Autodesk Fusion 360 part; units mm, degrees
(part 6 of 8)
equation "d534 = ( ledCenter - ledHeight / 2 + diffuserClearance + diffuserSideWall ) + faceOriginV"
equation "d535 = ( ( ( caseWidth - ledWidth ) / 2 + diffuserClearance + diffuserSideWall ) + ( ledWidth - 2 * ( diffuserClearance + diffuserSideWall ) ) ) - ( ( caseWidth - ledWidth ) / 2 + diffuserClearance + diffuserSideWall )"
equation "d536 = ( ( ( ledCenter - ledHeight / 2 + diffuserClearance + diffuserSideWall ) + faceOriginV ) + ( ledHeight - 2 * ( diffuserClearance + diffuserSideWall ) ) ) - ( ( ledCenter - ledHeight / 2 + diffuserClearance + diffuserSideWall ) + faceOriginV )"
equation "d537 = -( diffuserRearDepth + 1 mm )"
equation "d539 = ( caseWidth + ledWidth ) / 2 - diffuserSideWall - 1 mm"
equation "d540 = ( ledCenter - ledWireWidth / 2 ) + faceOriginV"
equation "d541 = ( ( ( caseWidth + ledWidth ) / 2 - diffuserSideWall - 1 mm ) + ( 5 mm ) ) - ( ( caseWidth + ledWidth ) / 2 - diffuserSideWall - 1 mm )"
equation "d542 = ( ( ( ledCenter - ledWireWidth / 2 ) + faceOriginV ) + ( ledWireWidth ) ) - ( ( ledCenter - ledWireWidth / 2 ) + faceOriginV )"
equation "d543 = -( diffuserRearDepth )"
equation "d545 = ( caseWidth - ledWidth ) / 2 + diffuserClearance - diffuserFlange - flangePocketClearance"
equation "d546 = ( ledCenter - ledHeight / 2 + diffuserClearance - diffuserFlange - flangePocketClearance ) + faceOriginV"
equation "d547 = ( ( ( caseWidth - ledWidth ) / 2 + diffuserClearance - diffuserFlange - flangePocketClearance ) + ( ledWidth - 2 * diffuserClearance + 2 * ( diffuserFlange + flangePocketClearance ) ) ) - ( ( caseWidth - ledWidth ) / 2 + diffuserClearance - diffuserFlange - flangePocketClearance )"
equation "d548 = ( ( ( ledCenter - ledHeight / 2 + diffuserClearance - diffuserFlange - flangePocketClearance ) + faceOriginV ) + ( ledHeight - 2 * diffuserClearance + 2 * ( diffuserFlange + flangePocketClearance ) ) ) - ( ( ledCenter - ledHeight / 2 + diffuserClearance - diffuserFlange - flangePocketClearance ) + faceOriginV )"
equation "d549 = -( diffuserRearDepth - shellWall - carrierClearance + 0.2 mm )"
equation "d551 = ( caseWidth - ledWidth ) / 2 - 0.2 mm"
equation "d552 = ( faceLength - ( shellWall + carrierClearance ) / cos(caseTilt) - ( shellWall + carrierClearance + carrierThickness ) * tan(caseTilt) - carrierRim + 0.4 mm ) + faceOriginV"
equation "d553 = ( ( ( caseWidth - ledWidth ) / 2 - 0.2 mm ) + ( ledWidth + 0.4 mm ) ) - ( ( caseWidth - ledWidth ) / 2 - 0.2 mm )"
equation "d554 = ( ( ( faceLength - ( shellWall + carrierClearance ) / cos(caseTilt) - ( shellWall + carrierClearance + carrierThickness ) * tan(caseTilt) - carrierRim + 0.4 mm ) + faceOriginV ) + ( 4 mm ) ) - ( ( faceLength - ( shellWall + carrierClearance ) / cos(caseTilt) - ( shellWall + carrierClearance + carrierThickness ) * tan(caseTilt) - carrierRim + 0.4 mm ) + faceOriginV )"
equation "d555 = -( ledTrayDepth + ledTrayThickness - shellWall - carrierClearance )"
equation "d557 = -ledTrayDepth"
equation "d559 = ( caseWidth - ledWidth ) / 2 - 0.2 mm"
equation "d560 = ( ledCenter - ledHeight / 2 - 0.2 mm ) + faceOriginV"
equation "d561 = ( ( ( caseWidth - ledWidth ) / 2 - 0.2 mm ) + ( ledWidth + 0.4 mm ) ) - ( ( caseWidth - ledWidth ) / 2 - 0.2 mm )"
equation "d562 = ( ( ( ledCenter - ledHeight / 2 - 0.2 mm ) + faceOriginV ) + ( ( faceLength - ( shellWall + carrierClearance ) / cos(caseTilt) - ( ledTrayDepth + ledTrayThickness ) * tan(caseTilt) ) - ( ledCenter - ledHeight / 2 - 0.2 mm ) ) ) - ( ( ledCenter - ledHeight / 2 - 0.2 mm ) + faceOriginV )"
equation "d563 = -( ledTrayThickness )"
equation "d565 = ( caseWidth + ledWidth ) / 2 - 2 mm"
equation "d566 = ( ledCenter - ledWireWidth / 2 ) + faceOriginV"
equation "d567 = ( ( ( caseWidth + ledWidth ) / 2 - 2 mm ) + ( 4 mm ) ) - ( ( caseWidth + ledWidth ) / 2 - 2 mm )"
equation "d568 = ( ( ( ledCenter - ledWireWidth / 2 ) + faceOriginV ) + ( ledWireWidth ) ) - ( ( ledCenter - ledWireWidth / 2 ) + faceOriginV )"
equation "d569 = -( ledTrayThickness + 1 mm )"
equation "d571 = layoutGap + ( displayWidth - oledBoardWidth ) / 2"
equation "d572 = ( controlCenter - oledBoardLength / 2 ) + faceOriginV"
equation "d573 = ( ( layoutGap + ( displayWidth - oledBoardWidth ) / 2 ) + ( oledBoardWidth ) ) - ( layoutGap + ( displayWidth - oledBoardWidth ) / 2 )"
equation "d574 = ( ( ( controlCenter - oledBoardLength / 2 ) + faceOriginV ) + ( 3 mm ) ) - ( ( controlCenter - oledBoardLength / 2 ) + faceOriginV )"
equation "d575 = -( oledPcbFrontDepth )"
equation "d577 = layoutGap + ( displayWidth - oledBoardWidth ) / 2"
equation "d578 = ( controlCenter + oledBoardLength / 2 - 5 mm ) + faceOriginV"
equation "d579 = ( ( layoutGap + ( displayWidth - oledBoardWidth ) / 2 ) + ( oledBoardWidth ) ) - ( layoutGap + ( displayWidth - oledBoardWidth ) / 2 )"
equation "d580 = ( ( ( controlCenter + oledBoardLength / 2 - 5 mm ) + faceOriginV ) + ( 3 mm ) ) - ( ( controlCenter + oledBoardLength / 2 - 5 mm ) + faceOriginV )"
equation "d581 = -( oledPcbFrontDepth )"
equation "d583 = layoutGap + ( displayWidth - oledBoardWidth ) / 2 - oledFitClearance"
equation "d584 = ( controlCenter - oledBoardLength / 2 - oledFitClearance ) + faceOriginV"
equation "d585 = ( ( layoutGap + ( displayWidth - oledBoardWidth ) / 2 - oledFitClearance ) + ( oledBoardWidth + 2 * oledFitClearance ) ) - ( layoutGap + ( displayWidth - oledBoardWidth ) / 2 - oledFitClearance )"
equation "d586 = ( ( ( controlCenter - oledBoardLength / 2 - oledFitClearance ) + faceOriginV ) + ( oledBoardLength + 2 * oledFitClearance ) ) - ( ( controlCenter - oledBoardLength / 2 - oledFitClearance ) + faceOriginV )"
equation "d587 = -( oledBackDepth + oledFitClearance - shellWall - carrierClearance )"
equation "d589 = -( oledBackDepth + oledFitClearance )"
equation "d592 = ( controlCenter - 18 mm ) + faceOriginV"
equation "d593 = ( ( 18 mm ) + ( 14 mm ) ) - ( 18 mm )"
equation "d594 = ( ( ( controlCenter - 18 mm ) + faceOriginV ) + ( 1 mm ) ) - ( ( controlCenter - 18 mm ) + faceOriginV )"
equation "d595 = -( oledBackDepth + oledFitClearance + 2 mm - shellWall - carrierClearance )"
equation "d598 = ( controlCenter - 18 mm ) + faceOriginV"
equation "d599 = ( ( 18 mm ) + ( 14 mm ) ) - ( 18 mm )"
equation "d600 = ( ( ( controlCenter - 18 mm ) + faceOriginV ) + ( 4 mm ) ) - ( ( controlCenter - 18 mm ) + faceOriginV )"
equation "d601 = -( 2 mm )"
equation "d604 = ( controlCenter + 12.8 mm ) + faceOriginV"
equation "d605 = ( ( 18 mm ) + ( 14 mm ) ) - ( 18 mm )"
equation "d606 = ( ( ( controlCenter + 12.8 mm ) + faceOriginV ) + ( 3.8 mm ) ) - ( ( controlCenter + 12.8 mm ) + faceOriginV )"
equation "d607 = -( ledTrayThickness )"
equation "d610 = ( controlCenter + 13 mm ) + faceOriginV"
equation "d611 = ( ( 18 mm ) + ( 14 mm ) ) - ( 18 mm )"
equation "d612 = ( ( ( controlCenter + 13 mm ) + faceOriginV ) + ( 2 mm ) ) - ( ( controlCenter + 13 mm ) + faceOriginV )"
equation "d613 = -( 2 mm )"
equation "d615 = layoutGap + ( displayWidth - oledBoardWidth ) / 2 - oledFitClearance"
equation "d616 = ( controlCenter - oledBoardLength / 2 - oledFitClearance ) + faceOriginV"
equation "d617 = ( ( layoutGap + ( displayWidth - oledBoardWidth ) / 2 - oledFitClearance ) + ( oledBoardWidth + 2 * oledFitClearance ) ) - ( layoutGap + ( displayWidth - oledBoardWidth ) / 2 - oledFitClearance )"
equation "d618 = ( ( ( controlCenter - oledBoardLength / 2 - oledFitClearance ) + faceOriginV ) + ( oledBoardLength + 2 * oledFitClearance ) ) - ( ( controlCenter - oledBoardLength / 2 - oledFitClearance ) + faceOriginV )"
equation "d619 = -( oledBackDepth + oledFitClearance - shellWall - carrierClearance )"
equation "d621 = pcbTopHeight + 4 mm"
equation "d624 = ( pcbFront + ( pcbLength - pcbHolePitchY ) / 2 + 0 * pcbHolePitchY ) - 2 mm"
equation "d625 = ( ( 3.2 mm ) + ( 1.6 mm ) ) - ( 3.2 mm )"
equation "d626 = ( ( ( pcbFront + ( pcbLength - pcbHolePitchY ) / 2 + 0 * pcbHolePitchY ) - 2 mm ) + ( 4 mm ) ) - ( ( pcbFront + ( pcbLength - pcbHolePitchY ) / 2 + 0 * pcbHolePitchY ) - 2 mm )"
equation "d630 = ( pcbFront + ( pcbLength - pcbHolePitchY ) / 2 + 0 * pcbHolePitchY ) - 2 mm"
equation "d631 = ( ( 3.2 mm ) + ( 3.8 mm ) ) - ( 3.2 mm )"
equation "d632 = ( ( ( pcbFront + ( pcbLength - pcbHolePitchY ) / 2 + 0 * pcbHolePitchY ) - 2 mm ) + ( 4 mm ) ) - ( ( pcbFront + ( pcbLength - pcbHolePitchY ) / 2 + 0 * pcbHolePitchY ) - 2 mm )"
equation "d635 = pcbLeft + ( pcbWidth - pcbHolePitchX ) / 2 + 0 * pcbHolePitchX"
equation "d636 = pcbFront + ( pcbLength - pcbHolePitchY ) / 2 + 0 * pcbHolePitchY"
equation "d637 = pcbPostDiameter"
equation "d640 = pcbLeft + ( pcbWidth - pcbHolePitchX ) / 2 + 0 * pcbHolePitchX"
equation "d641 = pcbFront + ( pcbLength - pcbHolePitchY ) / 2 + 0 * pcbHolePitchY"
equation "d642 = pcbPostPilot"
equation "d645 = caseWidth - 4.8 mm"
equation "d646 = ( pcbFront + ( pcbLength - pcbHolePitchY ) / 2 + 0 * pcbHolePitchY ) - 2 mm"
equation "d647 = ( ( caseWidth - 4.8 mm ) + ( 1.6 mm ) ) - ( caseWidth - 4.8 mm )"
equation "d648 = ( ( ( pcbFront + ( pcbLength - pcbHolePitchY ) / 2 + 0 * pcbHolePitchY ) - 2 mm ) + ( 4 mm ) ) - ( ( pcbFront + ( pcbLength - pcbHolePitchY ) / 2 + 0 * pcbHolePitchY ) - 2 mm )"
equation "d651 = caseWidth - 7 mm"
equation "d652 = ( pcbFront + ( pcbLength - pcbHolePitchY ) / 2 + 0 * pcbHolePitchY ) - 2 mm"
equation "d653 = ( ( caseWidth - 7 mm ) + ( 3.8 mm ) ) - ( caseWidth - 7 mm )"
equation "d654 = ( ( ( pcbFront + ( pcbLength - pcbHolePitchY ) / 2 + 0 * pcbHolePitchY ) - 2 mm ) + ( 4 mm ) ) - ( ( pcbFront + ( pcbLength - pcbHolePitchY ) / 2 + 0 * pcbHolePitchY ) - 2 mm )"
equation "d657 = pcbLeft + ( pcbWidth - pcbHolePitchX ) / 2 + 1 * pcbHolePitchX"
equation "d658 = pcbFront + ( pcbLength - pcbHolePitchY ) / 2 + 0 * pcbHolePitchY"
equation "d659 = pcbPostDiameter"
equation "d662 = pcbLeft + ( pcbWidth - pcbHolePitchX ) / 2 + 1 * pcbHolePitchX"
equation "d663 = pcbFront + ( pcbLength - pcbHolePitchY ) / 2 + 0 * pcbHolePitchY"
equation "d664 = pcbPostPilot"
equation "d668 = ( pcbFront + ( pcbLength - pcbHolePitchY ) / 2 + 1 * pcbHolePitchY ) - 2 mm"
equation "d669 = ( ( 3.2 mm ) + ( 1.6 mm ) ) - ( 3.2 mm )"
equation "d670 = ( ( ( pcbFront + ( pcbLength - pcbHolePitchY ) / 2 + 1 * pcbHolePitchY ) - 2 mm ) + ( 4 mm ) ) - ( ( pcbFront + ( pcbLength - pcbHolePitchY ) / 2 + 1 * pcbHolePitchY ) - 2 mm )"
equation "d674 = ( pcbFront + ( pcbLength - pcbHolePitchY ) / 2 + 1 * pcbHolePitchY ) - 2 mm"
equation "d675 = ( ( 3.2 mm ) + ( 3.8 mm ) ) - ( 3.2 mm )"
equation "d676 = ( ( ( pcbFront + ( pcbLength - pcbHolePitchY ) / 2 + 1 * pcbHolePitchY ) - 2 mm ) + ( 4 mm ) ) - ( ( pcbFront + ( pcbLength - pcbHolePitchY ) / 2 + 1 * pcbHolePitchY ) - 2 mm )"
equation "d679 = pcbLeft + ( pcbWidth - pcbHolePitchX ) / 2 + 0 * pcbHolePitchX"
equation "d680 = pcbFront + ( pcbLength - pcbHolePitchY ) / 2 + 1 * pcbHolePitchY"
equation "d681 = pcbPostDiameter"
equation "d684 = pcbLeft + ( pcbWidth - pcbHolePitchX ) / 2 + 0 * pcbHolePitchX"
equation "d685 = pcbFront + ( pcbLength - pcbHolePitchY ) / 2 + 1 * pcbHolePitchY"
equation "d686 = pcbPostPilot"
equation "d689 = caseWidth - 4.8 mm"
equation "d690 = ( pcbFront + ( pcbLength - pcbHolePitchY ) / 2 + 1 * pcbHolePitchY ) - 2 mm"
equation "d691 = ( ( caseWidth - 4.8 mm ) + ( 1.6 mm ) ) - ( caseWidth - 4.8 mm )"
equation "d692 = ( ( ( pcbFront + ( pcbLength - pcbHolePitchY ) / 2 + 1 * pcbHolePitchY ) - 2 mm ) + ( 4 mm ) ) - ( ( pcbFront + ( pcbLength - pcbHolePitchY ) / 2 + 1 * pcbHolePitchY ) - 2 mm )"
equation "d695 = caseWidth - 7 mm"
equation "d696 = ( pcbFront + ( pcbLength - pcbHolePitchY ) / 2 + 1 * pcbHolePitchY ) - 2 mm"
equation "d697 = ( ( caseWidth - 7 mm ) + ( 3.8 mm ) ) - ( caseWidth - 7 mm )"
equation "d698 = ( ( ( pcbFront + ( pcbLength - pcbHolePitchY ) / 2 + 1 * pcbHolePitchY ) - 2 mm ) + ( 4 mm ) ) - ( ( pcbFront + ( pcbLength - pcbHolePitchY ) / 2 + 1 * pcbHolePitchY ) - 2 mm )"
equation "d701 = pcbLeft + ( pcbWidth - pcbHolePitchX ) / 2 + 1 * pcbHolePitchX"
equation "d702 = pcbFront + ( pcbLength - pcbHolePitchY ) / 2 + 1 * pcbHolePitchY"
equation "d703 = pcbPostDiameter"
equation "d706 = pcbLeft + ( pcbWidth - pcbHolePitchX ) / 2 + 1 * pcbHolePitchX"
equation "d707 = pcbFront + ( pcbLength - pcbHolePitchY ) / 2 + 1 * pcbHolePitchY"
equation "d708 = pcbPostPilot"
equation "d711 = -( carrierBossDepth + carrierClearance )"
equation "d713 = mountSideX"
equation "d714 = ( mountFrontV ) + faceOriginV"
equation "d715 = mountBossDiameter"
equation "d716 = -( carrierClearance )"
equation "d718 = mountSideX"
equation "d719 = ( mountFrontV ) + faceOriginV"
equation "d720 = insertPilotDiameter"
equation "d721 = carrierClearance + 0.1 mm"
equation "d723 = caseWidth - mountSideX"
equation "d724 = ( mountFrontV ) + faceOriginV"
equation "d725 = mountBossDiameter"
equation "d726 = -( carrierClearance )"
equation "d728 = caseWidth - mountSideX"
equation "d729 = ( mountFrontV ) + faceOriginV"
equation "d730 = insertPilotDiameter"
equation "d731 = carrierClearance + 0.1 mm"
equation "d733 = mountSideX"
equation "d734 = ( mountRearV ) + faceOriginV"
equation "d735 = mountBossDiameter"
equation "d736 = -( carrierClearance )"
equation "d738 = mountSideX"
equation "d739 = ( mountRearV ) + faceOriginV"
equation "d740 = insertPilotDiameter"
equation "d741 = carrierClearance + 0.1 mm"
equation "d743 = mountSideX"
equation "d744 = ( mountRearV ) + faceOriginV"
equation "d745 = mountBossDiameter + 2 * mountPocketClearance"
equation "d746 = carrierBossDepth + carrierClearance"
equation "d748 = mountSideX"
equation "d749 = ( mountRearV ) + faceOriginV"
equation "d750 = m2Clearance"
equation "d751 = -( carrierPadDepth )"
equation "d754 = caseLength - 3 mm"
equation "d755 = bottomBossDiameter + 2 * bottomReliefClearance"
equation "d756 = rearHeight + 1 mm"
equation "d758 = caseWidth - mountSideX"
equation "d759 = ( mountRearV ) + faceOriginV"
equation "d760 = mountBossDiameter"
equation "d761 = -( carrierClearance )"
equation "d763 = caseWidth - mountSideX"
equation "d764 = ( mountRearV ) + faceOriginV"
equation "d765 = insertPilotDiameter"
equation "d766 = carrierClearance + 0.1 mm"
equation "d768 = caseWidth - mountSideX"
equation "d769 = ( mountRearV ) + faceOriginV"
equation "d770 = mountBossDiameter + 2 * mountPocketClearance"
equation "d771 = carrierBossDepth + carrierClearance"
equation "d773 = caseWidth - mountSideX"
equation "d774 = ( mountRearV ) + faceOriginV"
equation "d775 = m2Clearance"
equation "d776 = -( carrierPadDepth )"
equation "d778 = caseWidth - 20 mm"
equation "d779 = caseLength - 3 mm"
equation "d780 = bottomBossDiameter + 2 * bottomReliefClearance"
equation "d781 = rearHeight + 1 mm"
equation "pcbMountHeight = 22.3 mm" comment "Upper solder-side PCB seating face; components face bottom cover"
equation "pcbRailHeight = 27.8 mm" comment "Short screw bosses attach to continuous outer carrier rails"
equation "pcbRailThickness = 1.5 mm" comment "Mounting ear thickness"
equation "d788 = -( ( 0 ) * ( pcbFront ) + ( -1 ) * ( pcbRailHeight ) )"
equation "d789 = ( 1 ) * ( pcbFront ) + ( 0 ) * ( pcbRailHeight )"
equation "d790 = ( ( 1 ) * ( pcbRear ) + ( 0 ) * ( pcbRailHeight ) ) - ( ( 1 ) * ( pcbFront ) + ( 0 ) * ( pcbRailHeight ) )"
equation "d791 = -( ( ( 0 ) * ( pcbRear ) + ( -1 ) * ( frontHeight + pcbRear * tan(caseTilt) - ( shellWall + carrierClearance + carrierThickness - 0.3 mm ) / cos(caseTilt) ) ) - ( ( 0 ) * ( pcbRear ) + ( -1 ) * ( pcbRailHeight ) ) )"
equation "d792 = ( ( 0 ) * ( pcbFront ) + ( -1 ) * ( pcbRailHeight ) ) - ( ( 0 ) * ( pcbFront ) + ( -1 ) * ( frontHeight + pcbFront * tan(caseTilt) - ( shellWall + carrierClearance + carrierThickness - 0.3 mm ) / cos(caseTilt) ) )"
equation "d795 = caseWidth - 4.8 mm"
equation "d797 = -( ( 0 ) * ( pcbFront ) + ( -1 ) * ( pcbRailHeight ) )"
equation "d798 = ( 1 ) * ( pcbFront ) + ( 0 ) * ( pcbRailHeight )"
equation "d799 = ( ( 1 ) * ( pcbRear ) + ( 0 ) * ( pcbRailHeight ) ) - ( ( 1 ) * ( pcbFront ) + ( 0 ) * ( pcbRailHeight ) )"
equation "d800 = -( ( ( 0 ) * ( pcbRear ) + ( -1 ) * ( frontHeight + pcbRear * tan(caseTilt) - ( shellWall + carrierClearance + carrierThickness - 0.3 mm ) / cos(caseTilt) ) ) - ( ( 0 ) * ( pcbRear ) + ( -1 ) * ( pcbRailHeight ) ) )"
equation "d801 = ( ( 0 ) * ( pcbFront ) + ( -1 ) * ( pcbRailHeight ) ) - ( ( 0 ) * ( pcbFront ) + ( -1 ) * ( frontHeight + pcbFront * tan(caseTilt) - ( shellWall + carrierClearance + carrierThickness - 0.3 mm ) / cos(caseTilt) ) )"
equation "d804 = pcbRailHeight"
equation "d807 = ( pcbFront + ( pcbLength - pcbHolePitchY ) / 2 + 0 * pcbHolePitchY ) - 2.2 mm"
equation "d808 = ( ( 3.2 mm ) + ( 6 mm ) ) - ( 3.2 mm )"
equation "d809 = ( ( ( pcbFront + ( pcbLength - pcbHolePitchY ) / 2 + 0 * pcbHolePitchY ) - 2.2 mm ) + ( 4.4 mm ) ) - ( ( pcbFront + ( pcbLength - pcbHolePitchY ) / 2 + 0 * pcbHolePitchY ) - 2.2 mm )"
equation "d810 = pcbRailThickness"
equation "d812 = pcbLeft + ( pcbWidth - pcbHolePitchX ) / 2 + 0 * pcbHolePitchX"
equation "d813 = pcbFront + ( pcbLength - pcbHolePitchY ) / 2 + 0 * pcbHolePitchY"
equation "d814 = pcbPostDiameter"
equation "d815 = pcbPostHeight"
equation "d817 = pcbLeft + ( pcbWidth - pcbHolePitchX ) / 2 + 0 * pcbHolePitchX"
equation "d818 = pcbFront + ( pcbLength - pcbHolePitchY ) / 2 + 0 * pcbHolePitchY"
equation "d819 = pcbPostPilot"
equation "d822 = caseWidth - 9.2 mm"
equation "d823 = ( pcbFront + ( pcbLength - pcbHolePitchY ) / 2 + 0 * pcbHolePitchY ) - 2.2 mm"
equation "d824 = ( ( caseWidth - 9.2 mm ) + ( 6 mm ) ) - ( caseWidth - 9.2 mm )"
equation "d825 = ( ( ( pcbFront + ( pcbLength - pcbHolePitchY ) / 2 + 0 * pcbHolePitchY ) - 2.2 mm ) + ( 4.4 mm ) ) - ( ( pcbFront + ( pcbLength - pcbHolePitchY ) / 2 + 0 * pcbHolePitchY ) - 2.2 mm )"
equation "d826 = pcbRailThickness"
equation "d828 = pcbLeft + ( pcbWidth - pcbHolePitchX ) / 2 + 1 * pcbHolePitchX"
equation "d829 = pcbFront + ( pcbLength - pcbHolePitchY ) / 2 + 0 * pcbHolePitchY"
equation "d830 = pcbPostDiameter"
equation "d831 = pcbPostHeight"
equation "d833 = pcbLeft + ( pcbWidth - pcbHolePitchX ) / 2 + 1 * pcbHolePitchX"
equation "d834 = pcbFront + ( pcbLength - pcbHolePitchY ) / 2 + 0 * pcbHolePitchY"
equation "d835 = pcbPostPilot"
equation "d839 = ( pcbFront + ( pcbLength - pcbHolePitchY ) / 2 + 1 * pcbHolePitchY ) - 2.2 mm"
equation "d840 = ( ( 3.2 mm ) + ( 6 mm ) ) - ( 3.2 mm )"
equation "d841 = ( ( ( pcbFront + ( pcbLength - pcbHolePitchY ) / 2 + 1 * pcbHolePitchY ) - 2.2 mm ) + ( 4.4 mm ) ) - ( ( pcbFront + ( pcbLength - pcbHolePitchY ) / 2 + 1 * pcbHolePitchY ) - 2.2 mm )"
equation "d842 = pcbRailThickness"
equation "d844 = pcbLeft + ( pcbWidth - pcbHolePitchX ) / 2 + 0 * pcbHolePitchX"
equation "d845 = pcbFront + ( pcbLength - pcbHolePitchY ) / 2 + 1 * pcbHolePitchY"
equation "d846 = pcbPostDiameter"
equation "d847 = pcbPostHeight"
equation "d849 = pcbLeft + ( pcbWidth - pcbHolePitchX ) / 2 + 0 * pcbHolePitchX"
equation "d850 = pcbFront + ( pcbLength - pcbHolePitchY ) / 2 + 1 * pcbHolePitchY"
equation "d851 = pcbPostPilot"
equation "d854 = caseWidth - 9.2 mm"
equation "d855 = ( pcbFront + ( pcbLength - pcbHolePitchY ) / 2 + 1 * pcbHolePitchY ) - 2.2 mm"
equation "d856 = ( ( caseWidth - 9.2 mm ) + ( 6 mm ) ) - ( caseWidth - 9.2 mm )"
equation "d857 = ( ( ( pcbFront + ( pcbLength - pcbHolePitchY ) / 2 + 1 * pcbHolePitchY ) - 2.2 mm ) + ( 4.4 mm ) ) - ( ( pcbFront + ( pcbLength - pcbHolePitchY ) / 2 + 1 * pcbHolePitchY ) - 2.2 mm )"
equation "d858 = pcbRailThickness"
equation "d860 = pcbLeft + ( pcbWidth - pcbHolePitchX ) / 2 + 1 * pcbHolePitchX"
equation "d861 = pcbFront + ( pcbLength - pcbHolePitchY ) / 2 + 1 * pcbHolePitchY"
equation "d862 = pcbPostDiameter"
equation "d863 = pcbPostHeight"
equation "d865 = pcbLeft + ( pcbWidth - pcbHolePitchX ) / 2 + 1 * pcbHolePitchX"
equation "d866 = pcbFront + ( pcbLength - pcbHolePitchY ) / 2 + 1 * pcbHolePitchY"
equation "d867 = pcbPostPilot"
equation "holderWidth = 11.03147984 mm" comment "Exact 3MF X bounding width"
equation "holderLength = 9.74910164 mm" comment "Exact 3MF Y bounding length"
equation "holderHeight = 5.2 mm" comment "Exact 3MF bounding height"
equation "holderTopDepth = shellWall + carrierClearance + 7 mm" comment "Measured flange underside to holder top"
equation "holderBottomDepth = holderTopDepth + holderHeight" comment "Holder lower bearing plane"
equation "holderFit = 0.2 mm" comment "Provisional XY pocket clearance per side"
equation "holderFrameX = 18.4 mm" comment "Receiver outer width"
equation "holderFrameY = 17.6 mm" comment "Receiver outer length preserving OLED clearance"
equation "holderSwitchVoid = 16 mm" comment "Provisional switch lower-body clearance"
equation "holderHookOverlap = 0.3 mm" comment "Prototype retention overlap"
equation "holderHookThickness = 0.8 mm" comment "Snap retaining lip thickness"
equation "holderSpringWidth = 2 mm" comment "External spring width"
equation "holderSpringY = 3.7 mm" comment "Mesh-verified plastic edge band clear of contact exits"
equation "holderLidGap = 0.2 mm" comment "Normal clearance between holder underside and lid support"
equation "d884 = -( shellWall + carrierClearance + carrierThickness )"
equation "d886 = -holderTopDepth"
equation "d888 = -holderBottomDepth"
equation "d890 = -( shellWall + carrierClearance + carrierThickness + 1 mm )"
equation "d892 = -( holderBottomDepth + holderLidGap )"
equation "d894 = bottomThickness"
equation "d896 = ( layoutGap + keycapSize / 2 + 0 * keyPitch ) - holderFrameX / 2"
equation "d897 = ( ( keyRowOne ) - holderFrameY / 2 ) + faceOriginV"
equation "d898 = ( ( ( layoutGap + keycapSize / 2 + 0 * keyPitch ) - holderFrameX / 2 ) + ( holderFrameX ) ) - ( ( layoutGap + keycapSize / 2 + 0 * keyPitch ) - holderFrameX / 2 )"
equation "d899 = ( ( ( ( keyRowOne ) - holderFrameY / 2 ) + faceOriginV ) + ( holderFrameY ) ) - ( ( ( keyRowOne ) - holderFrameY / 2 ) + faceOriginV )"
equation "d900 = -( holderBottomDepth + holderHookThickness - shellWall - carrierClearance - carrierThickness )"
equation "d902 = ( layoutGap + keycapSize / 2 + 0 * keyPitch ) - holderSwitchVoid / 2"
equation "d903 = ( ( keyRowOne ) - holderSwitchVoid / 2 ) + faceOriginV"
equation "d904 = ( ( ( layoutGap + keycapSize / 2 + 0 * keyPitch ) - holderSwitchVoid / 2 ) + ( holderSwitchVoid ) ) - ( ( layoutGap + keycapSize / 2 + 0 * keyPitch ) - holderSwitchVoid / 2 )"
equation "d905 = ( ( ( ( keyRowOne ) - holderSwitchVoid / 2 ) + faceOriginV ) + ( holderSwitchVoid ) ) - ( ( ( keyRowOne ) - holderSwitchVoid / 2 ) + faceOriginV )"
equation "d906 = -( holderTopDepth - shellWall - carrierClearance - carrierThickness )"
equation "d908 = ( layoutGap + keycapSize / 2 + 0 * keyPitch ) - holderWidth / 2 - holderFit"
equation "d909 = ( ( keyRowOne ) - holderLength / 2 - holderFit ) + faceOriginV"
equation "d910 = ( ( ( layoutGap + keycapSize / 2 + 0 * keyPitch ) - holderWidth / 2 - holderFit ) + ( holderWidth + 2 * holderFit ) ) - ( ( layoutGap + keycapSize / 2 + 0 * keyPitch ) - holderWidth / 2 - holderFit )"
equation "d911 = ( ( ( ( keyRowOne ) - holderLength / 2 - holderFit ) + faceOriginV ) + ( holderLength + 2 * holderFit ) ) - ( ( ( keyRowOne ) - holderLength / 2 - holderFit ) + faceOriginV )"
equation "d912 = -( holderHeight + holderHookThickness + 0.2 mm )"
equation "d914 = ( layoutGap + keycapSize / 2 + 0 * keyPitch ) - holderFrameX / 2 - 0.1 mm"
equation "d915 = ( ( ( keyRowOne ) + holderSpringY ) - holderSpringWidth / 2 - 0.6 mm ) + faceOriginV"
equation "d916 = ( ( ( layoutGap + keycapSize / 2 + 0 * keyPitch ) - holderFrameX / 2 - 0.1 mm ) + ( holderFrameX / 2 - holderWidth / 2 - holderFit + 0.1 mm ) ) - ( ( layoutGap + keycapSize / 2 + 0 * keyPitch ) - holderFrameX / 2 - 0.1 mm )"
equation "d917 = ( ( ( ( ( keyRowOne ) + holderSpringY ) - holderSpringWidth / 2 - 0.6 mm ) + faceOriginV ) + ( 0.6 mm ) ) - ( ( ( ( keyRowOne ) + holderSpringY ) - holderSpringWidth / 2 - 0.6 mm ) + faceOriginV )"
equation "d918 = -( holderBottomDepth + holderHookThickness - shellWall - carrierClearance - carrierThickness - 1 mm + 0.2 mm )"
equation "d920 = ( layoutGap + keycapSize / 2 + 0 * keyPitch ) - holderFrameX / 2 - 0.1 mm"
equation "d921 = ( ( ( keyRowOne ) + holderSpringY ) + holderSpringWidth / 2 ) + faceOriginV"
equation "d922 = ( ( ( layoutGap + keycapSize / 2 + 0 * keyPitch ) - holderFrameX / 2 - 0.1 mm ) + ( holderFrameX / 2 - holderWidth / 2 - holderFit + 0.1 mm ) ) - ( ( layoutGap + keycapSize / 2 + 0 * keyPitch ) - holderFrameX / 2 - 0.1 mm )"
equation "d923 = ( ( ( ( ( keyRowOne ) + holderSpringY ) + holderSpringWidth / 2 ) + faceOriginV ) + ( 0.6 mm ) ) - ( ( ( ( keyRowOne ) + holderSpringY ) + holderSpringWidth / 2 ) + faceOriginV )"
equation "d924 = -( holderBottomDepth + holderHookThickness - shellWall - carrierClearance - carrierThickness - 1 mm + 0.2 mm )"
equation "d926 = ( layoutGap + keycapSize / 2 + 0 * keyPitch ) - holderFrameX / 2 + 0.8 mm"
equation "d927 = ( ( ( keyRowOne ) + holderSpringY ) - holderSpringWidth / 2 ) + faceOriginV"
equation "d928 = ( ( ( layoutGap + keycapSize / 2 + 0 * keyPitch ) - holderFrameX / 2 + 0.8 mm ) + ( holderFrameX / 2 - 0.8 mm - holderWidth / 2 - holderFit ) ) - ( ( layoutGap + keycapSize / 2 + 0 * keyPitch ) - holderFrameX / 2 + 0.8 mm )"
equation "d929 = ( ( ( ( ( keyRowOne ) + holderSpringY ) - holderSpringWidth / 2 ) + faceOriginV ) + ( holderSpringWidth ) ) - ( ( ( ( keyRowOne ) + holderSpringY ) - holderSpringWidth / 2 ) + faceOriginV )"
equation "d930 = -( holderHeight + holderHookThickness + 0.2 mm )"
equation "d932 = ( layoutGap + keycapSize / 2 + 0 * keyPitch ) - holderFrameX / 2"
equation "d933 = ( ( ( keyRowOne ) + holderSpringY ) - holderSpringWidth / 2 ) + faceOriginV"
equation "d934 = ( ( ( layoutGap + keycapSize / 2 + 0 * keyPitch ) - holderFrameX / 2 ) + ( holderFrameX / 2 - holderWidth / 2 + holderHookOverlap ) ) - ( ( layoutGap + keycapSize / 2 + 0 * keyPitch ) - holderFrameX / 2 )"
equation "d935 = ( ( ( ( ( keyRowOne ) + holderSpringY ) - holderSpringWidth / 2 ) + faceOriginV ) + ( holderSpringWidth ) ) - ( ( ( ( keyRowOne ) + holderSpringY ) - holderSpringWidth / 2 ) + faceOriginV )"
equation "d936 = -( holderHookThickness )"
equation "d939 = ( layoutGap + keycapSize / 2 + 0 * keyPitch ) + holderWidth / 2 + holderFit"
equation "d940 = ( ( ( keyRowOne ) + holderSpringY ) - holderSpringWidth / 2 - 0.6 mm ) + faceOriginV"
equation "d941 = ( ( ( layoutGap + keycapSize / 2 + 0 * keyPitch ) + holderWidth / 2 + holderFit ) + ( holderFrameX / 2 - holderWidth / 2 - holderFit + 0.1 mm ) ) - ( ( layoutGap + keycapSize / 2 + 0 * keyPitch ) + holderWidth / 2 + holderFit )"
equation "d942 = ( ( ( ( ( keyRowOne ) + holderSpringY ) - holderSpringWidth / 2 - 0.6 mm ) + faceOriginV ) + ( 0.6 mm ) ) - ( ( ( ( keyRowOne ) + holderSpringY ) - holderSpringWidth / 2 - 0.6 mm ) + faceOriginV )"
equation "d943 = -( holderBottomDepth + holderHookThickness - shellWall - carrierClearance - carrierThickness - 1 mm + 0.2 mm )"
equation "d945 = ( layoutGap + keycapSize / 2 + 0 * keyPitch ) + holderWidth / 2 + holderFit"
equation "d946 = ( ( ( keyRowOne ) + holderSpringY ) + holderSpringWidth / 2 ) + faceOriginV"
equation "d947 = ( ( ( layoutGap + keycapSize / 2 + 0 * keyPitch ) + holderWidth / 2 + holderFit ) + ( holderFrameX / 2 - holderWidth / 2 - holderFit + 0.1 mm ) ) - ( ( layoutGap + keycapSize / 2 + 0 * keyPitch ) + holderWidth / 2 + holderFit )"
equation "d948 = ( ( ( ( ( keyRowOne ) + holderSpringY ) + holderSpringWidth / 2 ) + faceOriginV ) + ( 0.6 mm ) ) - ( ( ( ( keyRowOne ) + holderSpringY ) + holderSpringWidth / 2 ) + faceOriginV )"
equation "d949 = -( holderBottomDepth + holderHookThickness - shellWall - carrierClearance - carrierThickness - 1 mm + 0.2 mm )"
equation "d951 = ( layoutGap + keycapSize / 2 + 0 * keyPitch ) + holderWidth / 2 + holderFit"
equation "d952 = ( ( ( keyRowOne ) + holderSpringY ) - holderSpringWidth / 2 ) + faceOriginV"
equation "d953 = ( ( ( layoutGap + keycapSize / 2 + 0 * keyPitch ) + holderWidth / 2 + holderFit ) + ( holderFrameX / 2 - 0.8 mm - holderWidth / 2 - holderFit ) ) - ( ( layoutGap + keycapSize / 2 + 0 * keyPitch ) + holderWidth / 2 + holderFit )"
equation "d954 = ( ( ( ( ( keyRowOne ) + holderSpringY ) - holderSpringWidth / 2 ) + faceOriginV ) + ( holderSpringWidth ) ) - ( ( ( ( keyRowOne ) + holderSpringY ) - holderSpringWidth / 2 ) + faceOriginV )"
equation "d955 = -( holderHeight + holderHookThickness + 0.2 mm )"
equation "d957 = ( layoutGap + keycapSize / 2 + 0 * keyPitch ) + holderWidth / 2 - holderHookOverlap"
equation "d958 = ( ( ( keyRowOne ) + holderSpringY ) - holderSpringWidth / 2 ) + faceOriginV"
equation "d959 = ( ( ( layoutGap + keycapSize / 2 + 0 * keyPitch ) + holderWidth / 2 - holderHookOverlap ) + ( holderFrameX / 2 - holderWidth / 2 + holderHookOverlap ) ) - ( ( layoutGap + keycapSize / 2 + 0 * keyPitch ) + holderWidth / 2 - holderHookOverlap )"
equation "d960 = ( ( ( ( ( keyRowOne ) + holderSpringY ) - holderSpringWidth / 2 ) + faceOriginV ) + ( holderSpringWidth ) ) - ( ( ( ( keyRowOne ) + holderSpringY ) - holderSpringWidth / 2 ) + faceOriginV )"
equation "d961 = -( holderHookThickness )"
equation "d964 = ( layoutGap + keycapSize / 2 + 0 * keyPitch ) + ( -2.5 mm ) - 1.2 mm"
equation "d965 = ( ( ( keyRowOne ) - 1.2 mm ) * cos(caseTilt) + ( holderBottomDepth + holderLidGap ) * sin(caseTilt) ) - 2.5 mm"
equation "d966 = ( ( ( layoutGap + keycapSize / 2 + 0 * keyPitch ) + ( -2.5 mm ) - 1.2 mm ) + ( 2.4 mm ) ) - ( ( layoutGap + keycapSize / 2 + 0 * keyPitch ) + ( -2.5 mm ) - 1.2 mm )"
equation "d967 = ( ( ( ( ( keyRowOne ) - 1.2 mm ) * cos(caseTilt) + ( holderBottomDepth + holderLidGap ) * sin(caseTilt) ) - 2.5 mm ) + ( 5 mm ) ) - ( ( ( ( keyRowOne ) - 1.2 mm ) * cos(caseTilt) + ( holderBottomDepth + holderLidGap ) * sin(caseTilt) ) - 2.5 mm )"
equation "d968 = ( frontHeight + ( ( keyRowOne ) - 1.2 mm ) * sin(caseTilt) - ( holderBottomDepth + holderLidGap ) * cos(caseTilt) ) - bottomThickness - 2 mm"
equation "d970 = ( layoutGap + keycapSize / 2 + 0 * keyPitch ) + ( -2.5 mm ) - 0.5 mm"
equation "d971 = ( ( ( keyRowOne ) - 1.2 mm ) * cos(caseTilt) + ( holderBottomDepth + holderLidGap ) * sin(caseTilt) ) - 1.5 mm"
equation "d972 = ( ( ( layoutGap + keycapSize / 2 + 0 * keyPitch ) + ( -2.5 mm ) - 0.5 mm ) + ( 1 mm ) ) - ( ( layoutGap + keycapSize / 2 + 0 * keyPitch ) + ( -2.5 mm ) - 0.5 mm )"
equation "d973 = ( ( ( ( ( keyRowOne ) - 1.2 mm ) * cos(caseTilt) + ( holderBottomDepth + holderLidGap ) * sin(caseTilt) ) - 1.5 mm ) + ( 3 mm ) ) - ( ( ( ( keyRowOne ) - 1.2 mm ) * cos(caseTilt) + ( holderBottomDepth + holderLidGap ) * sin(caseTilt) ) - 1.5 mm )"
equation "d974 = ( frontHeight + ( ( keyRowOne ) - 1.2 mm ) * sin(caseTilt) - ( holderBottomDepth + holderLidGap ) * cos(caseTilt) ) - bottomThickness + 0.5 mm"
equation "d976 = ( ( layoutGap + keycapSize / 2 + 0 * keyPitch ) + ( -2.5 mm ) - 0.5 mm ) - 0.1 mm"
equation "d977 = ( ( ( keyRowOne ) - 1.2 mm ) - 2 mm ) + faceOriginV"
equation "d978 = ( ( ( ( layoutGap + keycapSize / 2 + 0 * keyPitch ) + ( -2.5 mm ) - 0.5 mm ) - 0.1 mm ) + ( 1.2 mm ) ) - ( ( ( layoutGap + keycapSize / 2 + 0 * keyPitch ) + ( -2.5 mm ) - 0.5 mm ) - 0.1 mm )"
equation "d979 = ( ( ( ( ( keyRowOne ) - 1.2 mm ) - 2 mm ) + faceOriginV ) + ( 4 mm ) ) - ( ( ( ( keyRowOne ) - 1.2 mm ) - 2 mm ) + faceOriginV )"
equation "d980 = rearHeight"
equation "d982 = ( layoutGap + keycapSize / 2 + 0 * keyPitch ) + ( 2.5 mm ) - 1.2 mm"
equation "d983 = ( ( ( keyRowOne ) - 1.2 mm ) * cos(caseTilt) + ( holderBottomDepth + holderLidGap ) * sin(caseTilt) ) - 2.5 mm"
equation "d984 = ( ( ( layoutGap + keycapSize / 2 + 0 * keyPitch ) + ( 2.5 mm ) - 1.2 mm ) + ( 2.4 mm ) ) - ( ( layoutGap + keycapSize / 2 + 0 * keyPitch ) + ( 2.5 mm ) - 1.2 mm )"
equation "d985 = ( ( ( ( ( keyRowOne ) - 1.2 mm ) * cos(caseTilt) + ( holderBottomDepth + holderLidGap ) * sin(caseTilt) ) - 2.5 mm ) + ( 5 mm ) ) - ( ( ( ( keyRowOne ) - 1.2 mm ) * cos(caseTilt) + ( holderBottomDepth + holderLidGap ) * sin(caseTilt) ) - 2.5 mm )"
equation "d986 = ( frontHeight + ( ( keyRowOne ) - 1.2 mm ) * sin(caseTilt) - ( holderBottomDepth + holderLidGap ) * cos(caseTilt) ) - bottomThickness - 2 mm"
equation "d988 = ( layoutGap + keycapSize / 2 + 0 * keyPitch ) + ( 2.5 mm ) - 0.5 mm"
equation "d989 = ( ( ( keyRowOne ) - 1.2 mm ) * cos(caseTilt) + ( holderBottomDepth + holderLidGap ) * sin(caseTilt) ) - 1.5 mm"
equation "d990 = ( ( ( layoutGap + keycapSize / 2 + 0 * keyPitch ) + ( 2.5 mm ) - 0.5 mm ) + ( 1 mm ) ) - ( ( layoutGap + keycapSize / 2 + 0 * keyPitch ) + ( 2.5 mm ) - 0.5 mm )"
equation "d991 = ( ( ( ( ( keyRowOne ) - 1.2 mm ) * cos(caseTilt) + ( holderBottomDepth + holderLidGap ) * sin(caseTilt) ) - 1.5 mm ) + ( 3 mm ) ) - ( ( ( ( keyRowOne ) - 1.2 mm ) * cos(caseTilt) + ( holderBottomDepth + holderLidGap ) * sin(caseTilt) ) - 1.5 mm )"
equation "d992 = ( frontHeight + ( ( keyRowOne ) - 1.2 mm ) * sin(caseTilt) - ( holderBottomDepth + holderLidGap ) * cos(caseTilt) ) - bottomThickness + 0.5 mm"
equation "d994 = ( ( layoutGap + keycapSize / 2 + 0 * keyPitch ) + ( 2.5 mm ) - 0.5 mm ) - 0.1 mm"
equation "d995 = ( ( ( keyRowOne ) - 1.2 mm ) - 2 mm ) + faceOriginV"
equation "d996 = ( ( ( ( layoutGap + keycapSize / 2 + 0 * keyPitch ) + ( 2.5 mm ) - 0.5 mm ) - 0.1 mm ) + ( 1.2 mm ) ) - ( ( ( layoutGap + keycapSize / 2 + 0 * keyPitch ) + ( 2.5 mm ) - 0.5 mm ) - 0.1 mm )"
equation "d997 = ( ( ( ( ( keyRowOne ) - 1.2 mm ) - 2 mm ) + faceOriginV ) + ( 4 mm ) ) - ( ( ( ( keyRowOne ) - 1.2 mm ) - 2 mm ) + faceOriginV )"
equation "d998 = rearHeight"
equation "d1000 = ( layoutGap + keycapSize / 2 + 1 * keyPitch ) - holderFrameX / 2"
equation "d1001 = ( ( keyRowOne ) - holderFrameY / 2 ) + faceOriginV"
equation "d1002 = ( ( ( layoutGap + keycapSize / 2 + 1 * keyPitch ) - holderFrameX / 2 ) + ( holderFrameX ) ) - ( ( layoutGap + keycapSize / 2 + 1 * keyPitch ) - holderFrameX / 2 )"
equation "d1003 = ( ( ( ( keyRowOne ) - holderFrameY / 2 ) + faceOriginV ) + ( holderFrameY ) ) - ( ( ( keyRowOne ) - holderFrameY / 2 ) + faceOriginV )"
equation "d1004 = -( holderBottomDepth + holderHookThickness - shellWall - carrierClearance - carrierThickness )"
equation "d1006 = ( layoutGap + keycapSize / 2 + 1 * keyPitch ) - holderSwitchVoid / 2"
equation "d1007 = ( ( keyRowOne ) - holderSwitchVoid / 2 ) + faceOriginV"
equation "d1008 = ( ( ( layoutGap + keycapSize / 2 + 1 * keyPitch ) - holderSwitchVoid / 2 ) + ( holderSwitchVoid ) ) - ( ( layoutGap + keycapSize / 2 + 1 * keyPitch ) - holderSwitchVoid / 2 )"
equation "d1009 = ( ( ( ( keyRowOne ) - holderSwitchVoid / 2 ) + faceOriginV ) + ( holderSwitchVoid ) ) - ( ( ( keyRowOne ) - holderSwitchVoid / 2 ) + faceOriginV )"
equation "d1010 = -( holderTopDepth - shellWall - carrierClearance - carrierThickness )"
equation "d1012 = ( layoutGap + keycapSize / 2 + 1 * keyPitch ) - holderWidth / 2 - holderFit"
equation "d1013 = ( ( keyRowOne ) - holderLength / 2 - holderFit ) + faceOriginV"
equation "d1014 = ( ( ( layoutGap + keycapSize / 2 + 1 * keyPitch ) - holderWidth / 2 - holderFit ) + ( holderWidth + 2 * holderFit ) ) - ( ( layoutGap + keycapSize / 2 + 1 * keyPitch ) - holderWidth / 2 - holderFit )"
equation "d1015 = ( ( ( ( keyRowOne ) - holderLength / 2 - holderFit ) + faceOriginV ) + ( holderLength + 2 * holderFit ) ) - ( ( ( keyRowOne ) - holderLength / 2 - holderFit ) + faceOriginV )"
equation "d1016 = -( holderHeight + holderHookThickness + 0.2 mm )"
equation "d1018 = ( layoutGap + keycapSize / 2 + 1 * keyPitch ) - holderFrameX / 2 - 0.1 mm"
equation "d1019 = ( ( ( keyRowOne ) + holderSpringY ) - holderSpringWidth / 2 - 0.6 mm ) + faceOriginV"
equation "d1020 = ( ( ( layoutGap + keycapSize / 2 + 1 * keyPitch ) - holderFrameX / 2 - 0.1 mm ) + ( holderFrameX / 2 - holderWidth / 2 - holderFit + 0.1 mm ) ) - ( ( layoutGap + keycapSize / 2 + 1 * keyPitch ) - holderFrameX / 2 - 0.1 mm )"
equation "d1021 = ( ( ( ( ( keyRowOne ) + holderSpringY ) - holderSpringWidth / 2 - 0.6 mm ) + faceOriginV ) + ( 0.6 mm ) ) - ( ( ( ( keyRowOne ) + holderSpringY ) - holderSpringWidth / 2 - 0.6 mm ) + faceOriginV )"
equation "d1022 = -( holderBottomDepth + holderHookThickness - shellWall - carrierClearance - carrierThickness - 1 mm + 0.2 mm )"
equation "d1024 = ( layoutGap + keycapSize / 2 + 1 * keyPitch ) - holderFrameX / 2 - 0.1 mm"
equation "d1025 = ( ( ( keyRowOne ) + holderSpringY ) + holderSpringWidth / 2 ) + faceOriginV"
equation "d1026 = ( ( ( layoutGap + keycapSize / 2 + 1 * keyPitch ) - holderFrameX / 2 - 0.1 mm ) + ( holderFrameX / 2 - holderWidth / 2 - holderFit + 0.1 mm ) ) - ( ( layoutGap + keycapSize / 2 + 1 * keyPitch ) - holderFrameX / 2 - 0.1 mm )"
equation "d1027 = ( ( ( ( ( keyRowOne ) + holderSpringY ) + holderSpringWidth / 2 ) + faceOriginV ) + ( 0.6 mm ) ) - ( ( ( ( keyRowOne ) + holderSpringY ) + holderSpringWidth / 2 ) + faceOriginV )"
equation "d1028 = -( holderBottomDepth + holderHookThickness - shellWall - carrierClearance - carrierThickness - 1 mm + 0.2 mm )"
equation "d1030 = ( layoutGap + keycapSize / 2 + 1 * keyPitch ) - holderFrameX / 2 + 0.8 mm"
equation "d1031 = ( ( ( keyRowOne ) + holderSpringY ) - holderSpringWidth / 2 ) + faceOriginV"
equation "d1032 = ( ( ( layoutGap + keycapSize / 2 + 1 * keyPitch ) - holderFrameX / 2 + 0.8 mm ) + ( holderFrameX / 2 - 0.8 mm - holderWidth / 2 - holderFit ) ) - ( ( layoutGap + keycapSize / 2 + 1 * keyPitch ) - holderFrameX / 2 + 0.8 mm )"
equation "d1033 = ( ( ( ( ( keyRowOne ) + holderSpringY ) - holderSpringWidth / 2 ) + faceOriginV ) + ( holderSpringWidth ) ) - ( ( ( ( keyRowOne ) + holderSpringY ) - holderSpringWidth / 2 ) + faceOriginV )"
equation "d1034 = -( holderHeight + holderHookThickness + 0.2 mm )"
equation "d1036 = ( layoutGap + keycapSize / 2 + 1 * keyPitch ) - holderFrameX / 2"
equation "d1037 = ( ( ( keyRowOne ) + holderSpringY ) - holderSpringWidth / 2 ) + faceOriginV"
equation "d1038 = ( ( ( layoutGap + keycapSize / 2 + 1 * keyPitch ) - holderFrameX / 2 ) + ( holderFrameX / 2 - holderWidth / 2 + holderHookOverlap ) ) - ( ( layoutGap + keycapSize / 2 + 1 * keyPitch ) - holderFrameX / 2 )"
equation "d1039 = ( ( ( ( ( keyRowOne ) + holderSpringY ) - holderSpringWidth / 2 ) + faceOriginV ) + ( holderSpringWidth ) ) - ( ( ( ( keyRowOne ) + holderSpringY ) - holderSpringWidth / 2 ) + faceOriginV )"
equation "d1040 = -( holderHookThickness )"
equation "d1043 = ( layoutGap + keycapSize / 2 + 1 * keyPitch ) + holderWidth / 2 + holderFit"
equation "d1044 = ( ( ( keyRowOne ) + holderSpringY ) - holderSpringWidth / 2 - 0.6 mm ) + faceOriginV"
equation "d1045 = ( ( ( layoutGap + keycapSize / 2 + 1 * keyPitch ) + holderWidth / 2 + holderFit ) + ( holderFrameX / 2 - holderWidth / 2 - holderFit + 0.1 mm ) ) - ( ( layoutGap + keycapSize / 2 + 1 * keyPitch ) + holderWidth / 2 + holderFit )"
equation "d1046 = ( ( ( ( ( keyRowOne ) + holderSpringY ) - holderSpringWidth / 2 - 0.6 mm ) + faceOriginV ) + ( 0.6 mm ) ) - ( ( ( ( keyRowOne ) + holderSpringY ) - holderSpringWidth / 2 - 0.6 mm ) + faceOriginV )"
equation "d1047 = -( holderBottomDepth + holderHookThickness - shellWall - carrierClearance - carrierThickness - 1 mm + 0.2 mm )"
equation "d1049 = ( layoutGap + keycapSize / 2 + 1 * keyPitch ) + holderWidth / 2 + holderFit"
equation "d1050 = ( ( ( keyRowOne ) + holderSpringY ) + holderSpringWidth / 2 ) + faceOriginV"
equation "d1051 = ( ( ( layoutGap + keycapSize / 2 + 1 * keyPitch ) + holderWidth / 2 + holderFit ) + ( holderFrameX / 2 - holderWidth / 2 - holderFit + 0.1 mm ) ) - ( ( layoutGap + keycapSize / 2 + 1 * keyPitch ) + holderWidth / 2 + holderFit )"
equation "d1052 = ( ( ( ( ( keyRowOne ) + holderSpringY ) + holderSpringWidth / 2 ) + faceOriginV ) + ( 0.6 mm ) ) - ( ( ( ( keyRowOne ) + holderSpringY ) + holderSpringWidth / 2 ) + faceOriginV )"
equation "d1053 = -( holderBottomDepth + holderHookThickness - shellWall - carrierClearance - carrierThickness - 1 mm + 0.2 mm )"
equation "d1055 = ( layoutGap + keycapSize / 2 + 1 * keyPitch ) + holderWidth / 2 + holderFit"
equation "d1056 = ( ( ( keyRowOne ) + holderSpringY ) - holderSpringWidth / 2 ) + faceOriginV"
equation "d1057 = ( ( ( layoutGap + keycapSize / 2 + 1 * keyPitch ) + holderWidth / 2 + holderFit ) + ( holderFrameX / 2 - 0.8 mm - holderWidth / 2 - holderFit ) ) - ( ( layoutGap + keycapSize / 2 + 1 * keyPitch ) + holderWidth / 2 + holderFit )"
equation "d1058 = ( ( ( ( ( keyRowOne ) + holderSpringY ) - holderSpringWidth / 2 ) + faceOriginV ) + ( holderSpringWidth ) ) - ( ( ( ( keyRowOne ) + holderSpringY ) - holderSpringWidth / 2 ) + faceOriginV )"
equation "d1059 = -( holderHeight + holderHookThickness + 0.2 mm )"
equation "d1061 = ( layoutGap + keycapSize / 2 + 1 * keyPitch ) + holderWidth / 2 - holderHookOverlap"
equation "d1062 = ( ( ( keyRowOne ) + holderSpringY ) - holderSpringWidth / 2 ) + faceOriginV"
equation "d1063 = ( ( ( layoutGap + keycapSize / 2 + 1 * keyPitch ) + holderWidth / 2 - holderHookOverlap ) + ( holderFrameX / 2 - holderWidth / 2 + holderHookOverlap ) ) - ( ( layoutGap + keycapSize / 2 + 1 * keyPitch ) + holderWidth / 2 - holderHookOverlap )"
equation "d1064 = ( ( ( ( ( keyRowOne ) + holderSpringY ) - holderSpringWidth / 2 ) + faceOriginV ) + ( holderSpringWidth ) ) - ( ( ( ( keyRowOne ) + holderSpringY ) - holderSpringWidth / 2 ) + faceOriginV )"
equation "d1065 = -( holderHookThickness )"
equation "d1068 = ( layoutGap + keycapSize / 2 + 1 * keyPitch ) + ( -2.5 mm ) - 1.2 mm"
equation "d1069 = ( ( ( keyRowOne ) - 1.2 mm ) * cos(caseTilt) + ( holderBottomDepth + holderLidGap ) * sin(caseTilt) ) - 2.5 mm"
equation "d1070 = ( ( ( layoutGap + keycapSize / 2 + 1 * keyPitch ) + ( -2.5 mm ) - 1.2 mm ) + ( 2.4 mm ) ) - ( ( layoutGap + keycapSize / 2 + 1 * keyPitch ) + ( -2.5 mm ) - 1.2 mm )"
equation "d1071 = ( ( ( ( ( keyRowOne ) - 1.2 mm ) * cos(caseTilt) + ( holderBottomDepth + holderLidGap ) * sin(caseTilt) ) - 2.5 mm ) + ( 5 mm ) ) - ( ( ( ( keyRowOne ) - 1.2 mm ) * cos(caseTilt) + ( holderBottomDepth + holderLidGap ) * sin(caseTilt) ) - 2.5 mm )"
equation "d1072 = ( frontHeight + ( ( keyRowOne ) - 1.2 mm ) * sin(caseTilt) - ( holderBottomDepth + holderLidGap ) * cos(caseTilt) ) - bottomThickness - 2 mm"
equation "d1074 = ( layoutGap + keycapSize / 2 + 1 * keyPitch ) + ( -2.5 mm ) - 0.5 mm"
equation "d1075 = ( ( ( keyRowOne ) - 1.2 mm ) * cos(caseTilt) + ( holderBottomDepth + holderLidGap ) * sin(caseTilt) ) - 1.5 mm"
equation "d1076 = ( ( ( layoutGap + keycapSize / 2 + 1 * keyPitch ) + ( -2.5 mm ) - 0.5 mm ) + ( 1 mm ) ) - ( ( layoutGap + keycapSize / 2 + 1 * keyPitch ) + ( -2.5 mm ) - 0.5 mm )"
equation "d1077 = ( ( ( ( ( keyRowOne ) - 1.2 mm ) * cos(caseTilt) + ( holderBottomDepth + holderLidGap ) * sin(caseTilt) ) - 1.5 mm ) + ( 3 mm ) ) - ( ( ( ( keyRowOne ) - 1.2 mm ) * cos(caseTilt) + ( holderBottomDepth + holderLidGap ) * sin(caseTilt) ) - 1.5 mm )"
equation "d1078 = ( frontHeight + ( ( keyRowOne ) - 1.2 mm ) * sin(caseTilt) - ( holderBottomDepth + holderLidGap ) * cos(caseTilt) ) - bottomThickness + 0.5 mm"
equation "d1080 = ( ( layoutGap + keycapSize / 2 + 1 * keyPitch ) + ( -2.5 mm ) - 0.5 mm ) - 0.1 mm"
equation "d1081 = ( ( ( keyRowOne ) - 1.2 mm ) - 2 mm ) + faceOriginV"
equation "d1082 = ( ( ( ( layoutGap + keycapSize / 2 + 1 * keyPitch ) + ( -2.5 mm ) - 0.5 mm ) - 0.1 mm ) + ( 1.2 mm ) ) - ( ( ( layoutGap + keycapSize / 2 + 1 * keyPitch ) + ( -2.5 mm ) - 0.5 mm ) - 0.1 mm )"
equation "d1083 = ( ( ( ( ( keyRowOne ) - 1.2 mm ) - 2 mm ) + faceOriginV ) + ( 4 mm ) ) - ( ( ( ( keyRowOne ) - 1.2 mm ) - 2 mm ) + faceOriginV )"
equation "d1084 = rearHeight"
equation "d1086 = ( layoutGap + keycapSize / 2 + 1 * keyPitch ) + ( 2.5 mm ) - 1.2 mm"
equation "d1087 = ( ( ( keyRowOne ) - 1.2 mm ) * cos(caseTilt) + ( holderBottomDepth + holderLidGap ) * sin(caseTilt) ) - 2.5 mm"
equation "d1088 = ( ( ( layoutGap + keycapSize / 2 + 1 * keyPitch ) + ( 2.5 mm ) - 1.2 mm ) + ( 2.4 mm ) ) - ( ( layoutGap + keycapSize / 2 + 1 * keyPitch ) + ( 2.5 mm ) - 1.2 mm )"
equation "d1089 = ( ( ( ( ( keyRowOne ) - 1.2 mm ) * cos(caseTilt) + ( holderBottomDepth + holderLidGap ) * sin(caseTilt) ) - 2.5 mm ) + ( 5 mm ) ) - ( ( ( ( keyRowOne ) - 1.2 mm ) * cos(caseTilt) + ( holderBottomDepth + holderLidGap ) * sin(caseTilt) ) - 2.5 mm )"
equation "d1090 = ( frontHeight + ( ( keyRowOne ) - 1.2 mm ) * sin(caseTilt) - ( holderBottomDepth + holderLidGap ) * cos(caseTilt) ) - bottomThickness - 2 mm"
equation "d1092 = ( layoutGap + keycapSize / 2 + 1 * keyPitch ) + ( 2.5 mm ) - 0.5 mm"
equation "d1093 = ( ( ( keyRowOne ) - 1.2 mm ) * cos(caseTilt) + ( holderBottomDepth + holderLidGap ) * sin(caseTilt) ) - 1.5 mm"
equation "d1094 = ( ( ( layoutGap + keycapSize / 2 + 1 * keyPitch ) + ( 2.5 mm ) - 0.5 mm ) + ( 1 mm ) ) - ( ( layoutGap + keycapSize / 2 + 1 * keyPitch ) + ( 2.5 mm ) - 0.5 mm )"
equation "d1095 = ( ( ( ( ( keyRowOne ) - 1.2 mm ) * cos(caseTilt) + ( holderBottomDepth + holderLidGap ) * sin(caseTilt) ) - 1.5 mm ) + ( 3 mm ) ) - ( ( ( ( keyRowOne ) - 1.2 mm ) * cos(caseTilt) + ( holderBottomDepth + holderLidGap ) * sin(caseTilt) ) - 1.5 mm )"
equation "d1096 = ( frontHeight + ( ( keyRowOne ) - 1.2 mm ) * sin(caseTilt) - ( holderBottomDepth + holderLidGap ) * cos(caseTilt) ) - bottomThickness + 0.5 mm"
equation "d1098 = ( ( layoutGap + keycapSize / 2 + 1 * keyPitch ) + ( 2.5 mm ) - 0.5 mm ) - 0.1 mm"
equation "d1099 = ( ( ( keyRowOne ) - 1.2 mm ) - 2 mm ) + faceOriginV"
equation "d1100 = ( ( ( ( layoutGap + keycapSize / 2 + 1 * keyPitch ) + ( 2.5 mm ) - 0.5 mm ) - 0.1 mm ) + ( 1.2 mm ) ) - ( ( ( layoutGap + keycapSize / 2 + 1 * keyPitch ) + ( 2.5 mm ) - 0.5 mm ) - 0.1 mm )"
equation "d1101 = ( ( ( ( ( keyRowOne ) - 1.2 mm ) - 2 mm ) + faceOriginV ) + ( 4 mm ) ) - ( ( ( ( keyRowOne ) - 1.2 mm ) - 2 mm ) + faceOriginV )"
equation "d1102 = rearHeight"
equation "d1104 = ( layoutGap + keycapSize / 2 + 2 * keyPitch ) - holderFrameX / 2"
equation "d1105 = ( ( keyRowOne ) - holderFrameY / 2 ) + faceOriginV"
equation "d1106 = ( ( ( layoutGap + keycapSize / 2 + 2 * keyPitch ) - holderFrameX / 2 ) + ( holderFrameX ) ) - ( ( layoutGap + keycapSize / 2 + 2 * keyPitch ) - holderFrameX / 2 )"
equation "d1107 = ( ( ( ( keyRowOne ) - holderFrameY / 2 ) + faceOriginV ) + ( holderFrameY ) ) - ( ( ( keyRowOne ) - holderFrameY / 2 ) + faceOriginV )"
equation "d1108 = -( holderBottomDepth + holderHookThickness - shellWall - carrierClearance - carrierThickness )"
equation "d1110 = ( layoutGap + keycapSize / 2 + 2 * keyPitch ) - holderSwitchVoid / 2"
equation "d1111 = ( ( keyRowOne ) - holderSwitchVoid / 2 ) + faceOriginV"
equation "d1112 = ( ( ( layoutGap + keycapSize / 2 + 2 * keyPitch ) - holderSwitchVoid / 2 ) + ( holderSwitchVoid ) ) - ( ( layoutGap + keycapSize / 2 + 2 * keyPitch ) - holderSwitchVoid / 2 )"
equation "d1113 = ( ( ( ( keyRowOne ) - holderSwitchVoid / 2 ) + faceOriginV ) + ( holderSwitchVoid ) ) - ( ( ( keyRowOne ) - holderSwitchVoid / 2 ) + faceOriginV )"
equation "d1114 = -( holderTopDepth - shellWall - carrierClearance - carrierThickness )"
equation "d1116 = ( layoutGap + keycapSize / 2 + 2 * keyPitch ) - holderWidth / 2 - holderFit"
equation "d1117 = ( ( keyRowOne ) - holderLength / 2 - holderFit ) + faceOriginV"
equation "d1118 = ( ( ( layoutGap + keycapSize / 2 + 2 * keyPitch ) - holderWidth / 2 - holderFit ) + ( holderWidth + 2 * holderFit ) ) - ( ( layoutGap + keycapSize / 2 + 2 * keyPitch ) - holderWidth / 2 - holderFit )"
equation "d1119 = ( ( ( ( keyRowOne ) - holderLength / 2 - holderFit ) + faceOriginV ) + ( holderLength + 2 * holderFit ) ) - ( ( ( keyRowOne ) - holderLength / 2 - holderFit ) + faceOriginV )"
equation "d1120 = -( holderHeight + holderHookThickness + 0.2 mm )"
equation "d1122 = ( layoutGap + keycapSize / 2 + 2 * keyPitch ) - holderFrameX / 2 - 0.1 mm"
equation "d1123 = ( ( ( keyRowOne ) + holderSpringY ) - holderSpringWidth / 2 - 0.6 mm ) + faceOriginV"
equation "d1124 = ( ( ( layoutGap + keycapSize / 2 + 2 * keyPitch ) - holderFrameX / 2 - 0.1 mm ) + ( holderFrameX / 2 - holderWidth / 2 - holderFit + 0.1 mm ) ) - ( ( layoutGap + keycapSize / 2 + 2 * keyPitch ) - holderFrameX / 2 - 0.1 mm )"
equation "d1125 = ( ( ( ( ( keyRowOne ) + holderSpringY ) - holderSpringWidth / 2 - 0.6 mm ) + faceOriginV ) + ( 0.6 mm ) ) - ( ( ( ( keyRowOne ) + holderSpringY ) - holderSpringWidth / 2 - 0.6 mm ) + faceOriginV )"
equation "d1126 = -( holderBottomDepth + holderHookThickness - shellWall - carrierClearance - carrierThickness - 1 mm + 0.2 mm )"
equation "d1128 = ( layoutGap + keycapSize / 2 + 2 * keyPitch ) - holderFrameX / 2 - 0.1 mm"
equation "d1129 = ( ( ( keyRowOne ) + holderSpringY ) + holderSpringWidth / 2 ) + faceOriginV"
equation "d1130 = ( ( ( layoutGap + keycapSize / 2 + 2 * keyPitch ) - holderFrameX / 2 - 0.1 mm ) + ( holderFrameX / 2 - holderWidth / 2 - holderFit + 0.1 mm ) ) - ( ( layoutGap + keycapSize / 2 + 2 * keyPitch ) - holderFrameX / 2 - 0.1 mm )"
equation "d1131 = ( ( ( ( ( keyRowOne ) + holderSpringY ) + holderSpringWidth / 2 ) + faceOriginV ) + ( 0.6 mm ) ) - ( ( ( ( keyRowOne ) + holderSpringY ) + holderSpringWidth / 2 ) + faceOriginV )"
equation "d1132 = -( holderBottomDepth + holderHookThickness - shellWall - carrierClearance - carrierThickness - 1 mm + 0.2 mm )"
equation "d1134 = ( layoutGap + keycapSize / 2 + 2 * keyPitch ) - holderFrameX / 2 + 0.8 mm"
equation "d1135 = ( ( ( keyRowOne ) + holderSpringY ) - holderSpringWidth / 2 ) + faceOriginV"
equation "d1136 = ( ( ( layoutGap + keycapSize / 2 + 2 * keyPitch ) - holderFrameX / 2 + 0.8 mm ) + ( holderFrameX / 2 - 0.8 mm - holderWidth / 2 - holderFit ) ) - ( ( layoutGap + keycapSize / 2 + 2 * keyPitch ) - holderFrameX / 2 + 0.8 mm )"
equation "d1137 = ( ( ( ( ( keyRowOne ) + holderSpringY ) - holderSpringWidth / 2 ) + faceOriginV ) + ( holderSpringWidth ) ) - ( ( ( ( keyRowOne ) + holderSpringY ) - holderSpringWidth / 2 ) + faceOriginV )"
equation "d1138 = -( holderHeight + holderHookThickness + 0.2 mm )"
equation "d1140 = ( layoutGap + keycapSize / 2 + 2 * keyPitch ) - holderFrameX / 2"